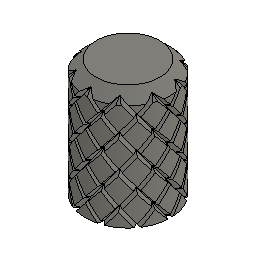
The RPA Device (Autodesk Fusion 360 archive; units mm, degrees)
design "M2.5 Standoff Knurled Cap"
part number: 2026-07-28-23-02-26-937
Autodesk Fusion 360 part; units mm, degrees
sketch "Sketch1" plane through (0, 0, 0) normal (0, 0, 1) x (1, 0, 0)
  line L0 (2.4, 1.3856) -> (0, 2.7713)
  line L1 (0, 2.7713) -> (-2.4, 1.3856)
  line L2 (-2.4, 1.3856) -> (-2.4, -1.3856)
  line L3 (-2.4, -1.3856) -> (0, -2.7713)
  line L4 (0, -2.7713) -> (2.4, -1.3856)
  line L5 (2.4, -1.3856) -> (2.4, 1.3856)
  circle A0 centre (0, 0) radius 4
  dimension "d1" = 2.4
  dimension "d2" = 8
  constraint coincident A0.centre origin
  constraint vertical L5
  measures "d1" distance of A0.centre L5
  measures "d2" diameter of A0
extrude "Extrude1" add sketch "Sketch1" along normal blind 10
extrude "Extrude2" add sketch "Sketch1" along normal blind 1 from surface at 10 contours L0 L1 L2 L3 L4 L5 | A0
chamfer "Chamfer1" distance 1 angle 45 1 edges at (-3.7293, -1.4465, 11) tangent chain off
coil "CoilPrimitive1" cut diameter 8 section triangle in size 1 on centre turns 1 pitch 30 right hand placed x (1, 0, 0) y (0, 1, 0) z (0, 0, 1) at (0, 0, 0)
mirror "Mirror1" about plane through (0, 0, 0) normal (0, 1, 0) of "CoilPrimitive1"
pattern_circular "C-Pattern2" count 10 over 360 about axis through (0, 0, 1.75) along (0, 0, 1) of "CoilPrimitive1", "Mirror1"
equation "d1 = 4.8 mm / 2"

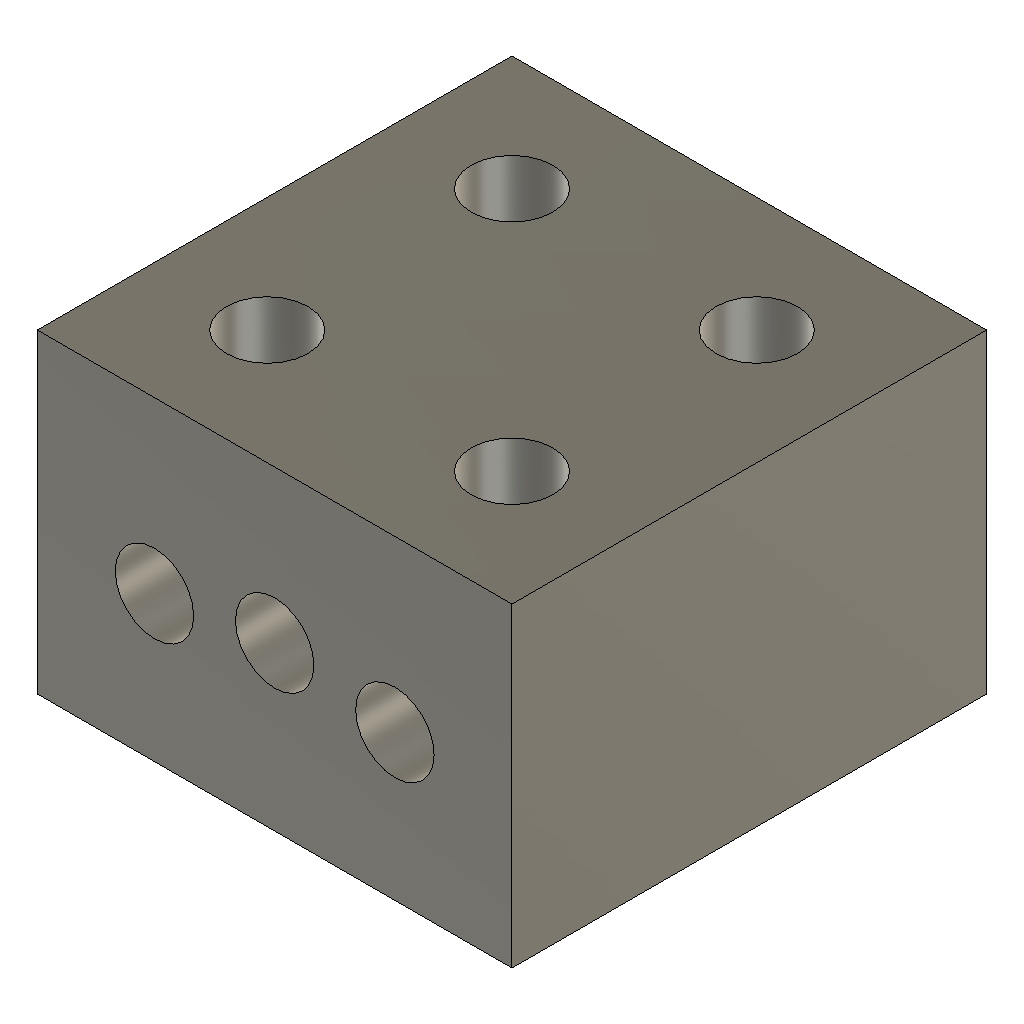
design "Heat Block Final"
part number: 2026-07-10-14-33-42-765
Autodesk Fusion 360 part; units mm, degrees
sketch "Sketch1" plane through (0, 0, 0) normal (0, 0, 1) x (1, 0, 0)
  line L0 (19.2, 19.2) -> (-19.2, 19.2)
  line L1 (-19.2, 19.2) -> (-19.2, -19.2)
  line L2 (-19.2, -19.2) -> (19.2, -19.2)
  line L3 (19.2, -19.2) -> (19.2, 19.2)
  line L4 (19.2, 19.2) -> (-19.2, -19.2) construction
  line L5 (-19.2, 19.2) -> (19.2, -19.2) construction
  circle A0 centre (0, 0) radius 3.175
  dimension "d1" = 38.4
  dimension "d2" = 38.4
  dimension "d53" = 6.35
  constraint horizontal L0
  constraint perpendicular L0 L1
  constraint parallel L0 L2
  constraint parallel L1 L3
  constraint coincident L4 A0.centre
  constraint coincident L5 A0.centre
  constraint coincident A0.centre origin
  measures "d1" distance of L1.end L2.end
  measures "d2" distance of L0.end L1.end
  measures "d53" diameter of A0
extrude "Extrude1" add sketch "Sketch1" along normal blind 25.5 contours L0 L1 L2 L3 | A0
extrude "Extrude7" cut sketch "Sketch1" along normal blind 20 contours A0
sketch "Sketch2" plane through (0, -19.2, 0) normal (0, -1, 0) x (1, 0, 0)
  line L0 (-19.2, 0) -> (19.2, 0)
  line L1 (19.2, 0) -> (19.2, 25.5)
  line L2 (19.2, 25.5) -> (-19.2, 25.5)
  line L3 (-19.2, 25.5) -> (-19.2, 0)
  circle A0 centre (0, 13.175) radius 3.175
  point P0 (0, 10)
  dimension "d5" = 6.35
  dimension "d6" = 10
  constraint vertical origin A0.centre
  constraint coincident A0 P0
  constraint vertical A0.centre P0
  measures "d5" diameter of A0
  measures "d6" distance of origin P0
sketch "Sketch3" plane through (19.2, 0, 0) normal (1, 0, 0) x (0, 1, 0)
  line L0 (-19.2, 0) -> (19.2, 0)
  line L1 (19.2, 0) -> (19.2, 25.5)
  line L2 (19.2, 25.5) -> (-19.2, 25.5)
  line L3 (-19.2, 25.5) -> (-19.2, 0)
  circle A0 centre (-10.2, 12.1) radius 1.5
  circle A1 centre (9.6, 12.1) radius 1.5
  line L4 (-19.2, 0) -> (-19.2, 25.5)
  point P0 (11.1, 12.1)
  point P1 (-11.7, 12.1)
  point P2 (9.6, 10.6)
  point P3 (-10.2, 10.6)
  dimension "d10" = 8.1
  dimension "d11" = 7.5
  dimension "d14" = 10.6
  dimension "d15" = 10.6
  dimension "d16" = 3
  dimension "d17" = 3
  constraint coincident A1 P0
  constraint coincident A0 P1
  constraint horizontal A0.centre P1
  constraint horizontal A1.centre P0
  constraint coincident A1 P2
  constraint vertical A0.centre P3
  constraint vertical A1.centre P2
  constraint coincident A0 P3
  measures "d10" distance of L1 P0
  measures "d11" distance of P1 L4
  measures "d14" distance of L0 P2
  measures "d15" distance of L0 P3
  measures "d16" diameter of A0
  measures "d17" diameter of A1
sketch "Sketch4" plane through (-19.2, 0, 0) normal (-1, 0, 0) x (0, -1, 0)
  line L0 (-19.2, 0) -> (19.2, 0)
  line L1 (19.2, 0) -> (19.2, 25.5)
  line L2 (19.2, 25.5) -> (-19.2, 25.5)
  line L3 (-19.2, 25.5) -> (-19.2, 0)
  circle A0 centre (-9.9, 11.7) radius 1.5
  circle A1 centre (10.2, 11.7) radius 1.5
  point P0 (11.7, 11.7)
  point P1 (10.2, 10.2)
  point P2 (-9.9, 10.2)
  point P3 (-11.4, 11.7)
  dimension "d18" = 3
  dimension "d19" = 3
  dimension "d20" = 10.2
  dimension "d21" = 10.2
  dimension "d22" = 7.8
  dimension "d23" = 7.5
  constraint coincident A1 P0
  constraint coincident A1 P1
  constraint coincident A0 P2
  constraint coincident A0 P3
  constraint horizontal A0.centre P3
  constraint vertical A0.centre P2
  constraint vertical A1.centre P1
  constraint horizontal A1.centre P0
  measures "d18" diameter of A0
  measures "d19" diameter of A1
  measures "d20" distance of L0 P1
  measures "d21" distance of L0 P2
  measures "d22" distance of L3 P3
  measures "d23" distance of L1 P0
sketch "Sketch5" plane through (0, 0, 25.5) normal (0, 0, 1) x (-1, 0, 0)
  line L0 (-19.2, -6.6) -> (19.2, -6.6)
  line L1 (19.2, -6.6) -> (19.2, 6.6)
  line L2 (19.2, 6.6) -> (-19.2, 6.6)
  line L3 (-19.2, 6.6) -> (-19.2, -6.6)
  line L4 (-19.2, -6.6) -> (19.2, 6.6) construction
  line L5 (19.2, -6.6) -> (-19.2, 6.6) construction
  line L6 (6.6, -19.2) -> (-6.6, -19.2)
  line L7 (-6.6, -19.2) -> (-6.6, 19.2)
  line L8 (-6.6, 19.2) -> (6.6, 19.2)
  line L9 (6.6, 19.2) -> (6.6, -19.2)
  line L10 (6.6, -19.2) -> (-6.6, 19.2) construction
  line L11 (-6.6, -19.2) -> (6.6, 19.2) construction
  circle A0 centre (9.9, -9.9) radius 3.3
  line L12 (0, -2.5) -> (0, -20)
  circle A1 centre (-9.9, -9.9) radius 3.3
  line L13 (-20, 0) -> (-2.5, 0)
  circle A2 centre (9.9, 9.9) radius 3.3
  circle A3 centre (-9.9, 9.9) radius 3.3
  point P0 (-19.2, -19.2)
  dimension "d39" = 13.2
  dimension "d40" = 13.2
  dimension "d41" = 3.3
  constraint horizontal L0
  constraint perpendicular L0 L1
  constraint parallel L0 L2
  constraint parallel L1 L3
  constraint coincident L4 origin
  constraint coincident L5 origin
  constraint coincident L3 P0
  constraint horizontal L6
  constraint perpendicular L6 L7
  constraint parallel L6 L8
  constraint parallel L7 L9
  constraint coincident L10 origin
  constraint coincident L11 origin
  constraint coincident P0 L6
  constraint tangent L0 A0
  constraint tangent L9 A0
  constraint symmetric A0 L12 A1
  constraint symmetric A0 L13 A2
  constraint symmetric A1 L13 A3
  measures "d39" distance of L0.end L1.end
  measures "d40" distance of L7.end L8.end
  measures "d41" radius of A0
extrude "Extrude2" cut sketch "Sketch5" against normal blind 19.5 contours A1 | A3 | A0 | A2
extrude "Extrude3" cut sketch "Sketch2" against normal blind 38.6 contours A0
sketch "Sketch6" plane through (0, -19.2, 0) normal (0, -1, 0) x (1, 0, 0)
  circle A0 centre (0, 13.175) radius 3.175
  line L0 (-19.2, 0) -> (19.2, 0)
  line L1 (19.2, 0) -> (19.2, 25.5)
  line L2 (19.2, 25.5) -> (-19.2, 25.5)
  line L3 (-19.2, 25.5) -> (-19.2, 0)
  line L4 (-13.2, 6) -> (-6.6, 6)
  line L5 (-13.2, 25.5) -> (-6.6, 25.5)
  line L6 (6.6, 6) -> (13.2, 6)
  line L7 (6.6, 25.5) -> (13.2, 25.5)
  circle A1 centre (9.725, 11.775) radius 3.175
  line L8 (0, 1.75) -> (0, 22.5)
  circle A2 centre (-9.725, 11.775) radius 3.175
  point P0 (9.9, 6)
  point P1 (-9.9, 6)
  point P2 (12.9, 11.775)
  point P3 (9.725, 8.6)
  dimension "d46" = 6.3
  dimension "d47" = 8.6
  dimension "d48" = 6.35
  constraint midpoint L6 P0
  constraint midpoint L4 P1
  constraint coincident A1 P2
  constraint coincident A1 P3
  constraint vertical A1.centre P3
  constraint horizontal A1.centre P2
  constraint symmetric A1 L8 A2
  measures "d46" distance of L1 P2
  measures "d47" distance of L0 P3
  measures "d48" diameter of A1
extrude "Extrude6" cut sketch "Sketch6" against normal blind 9.5 contours A1 | A2
mirror "Mirror1" about plane through (0, 0, 0) normal (0, 1, 0) of "Extrude6"
sketch "Sketch7" plane through (0, 0, 0) normal (0, 0, -1) x (1, 0, 0)
  circle A0 centre (0, 0) radius 3.175
  line L0 (19.2, -19.2) -> (19.2, 19.2)
  line L1 (19.2, 19.2) -> (-19.2, 19.2)
  line L2 (-19.2, 19.2) -> (-19.2, -19.2)
  line L3 (-19.2, -19.2) -> (19.2, -19.2)
  circle A1 centre (-9.9, -9.9) radius 3.3
  circle A2 centre (9.9, -9.9) radius 3.3
  circle A3 centre (-9.9, 9.9) radius 3.3
  circle A4 centre (9.9, 9.9) radius 3.3
  line L4 (19.2, 19.2) -> (19.2, -19.2)
  line L5 (19.2, -19.2) -> (-19.2, -19.2)
  line L6 (-19.2, -19.2) -> (-19.2, 19.2)
  line L7 (-19.2, 19.2) -> (19.2, 19.2)
  circle A5 centre (-9.9, 9.9) radius 1.5
  dimension "d56" = 3
  constraint concentric A3 A5
  measures "d56" diameter of A5
hole "Hole1" at (-9.9, -9.9, 0) direction (0, 0, 1) diameter 3 end up to surface (6 mm away) counterbore diameter 4 counterbore depth 1
pattern_circular "C-Pattern1" count 4 over 360 about axis through (0, 0, 1.75) along (0, 0, 1) of "Hole1"
equation "d41 = ( 6.6 / 2 ) * 1 mm"

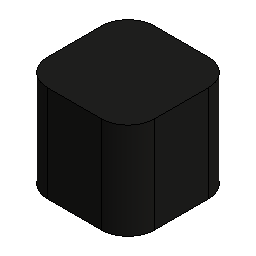
design "Lid Button Pressing Protrusion"
part number: 2026-08-27-08-52-42-225
part number: 2026-08-27-08-53-24-975
Autodesk Fusion 360 part; units mm, degrees
sketch "Sketch1" plane through (0, 0, 0) normal (0, 0, 1) x (1, 0, 0)
  line L0 (5, 5) -> (-5, 5)
  line L1 (-5, 5) -> (-5, -5)
  line L2 (-5, -5) -> (5, -5)
  line L3 (5, -5) -> (5, 5)
  line L4 (5, 5) -> (-5, -5) construction
  line L5 (-5, 5) -> (5, -5) construction
  dimension "d1" = 10
  dimension "d2" = 10
  constraint horizontal L0
  constraint perpendicular L0 L1
  constraint parallel L0 L2
  constraint parallel L1 L3
  constraint coincident L4 origin
  constraint coincident L5 origin
  measures "d1" distance of L1.end L2.end
  measures "d2" distance of L0.end L1.end
extrude "Extrude1" add sketch "Sketch1" along normal blind 9 makes body 1
fillet "Fillet1" radius 2.5 4 edges at (5, -5, 4.5) (5, 5, 4.5) (-5, 5, 4.5) (-5, -5, 4.5) on bodies 1
copy_body "Body->Comp1" bodies 1 removing the originals makes body 2 in component "Component"
component "Component" placed x (1, 0, 0) y (0, 1, 0) z (0, 0, 1) at (0, 0, 0)
